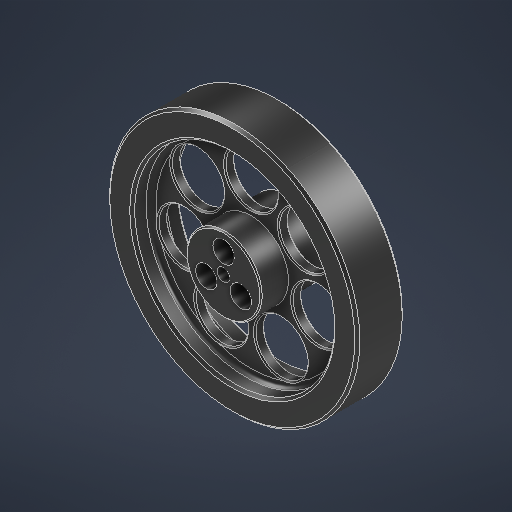
# Autodesk Inventor part: Flywheel with Cylinder
Saved by Autodesk Inventor 2026.3 (Build 303398000, 398)
## iProperties
Created: 2026-11-01
Part Number: Flywheel with Cylinder
Material: Steel
Document SubType Name: Modeling
Designer: ADMIN
Density: 7.85 g/cm^3
Appearance: Glossy - Black
Author: ADMIN
Autodesk Inventor part; units mm, degrees
ref_plane "YZ Plane" through (0, 0, 0) normal (1, 0, 0) x (0, 1, 0)
ref_plane "XZ Plane" through (0, 0, 0) normal (0, 1, 0) x (-1, 0, 0)
ref_plane "XY Plane" through (0, 0, 0) normal (0, 0, 1) x (1, 0, 0)
sketch "Sketch1" plane through (0, 0, 0) normal (0, 0, 1) x (1, 0, 0)
  circle A0 centre (0, 0) radius 50
  dimension "d0" = 100
  constraints: 1 centre point, 1 coincident
  measures "d0" diameter of A0
extrude "Extrusion1" add sketch "Sketch1" along normal mid plane 26
sketch "Sketch2" plane through (0, 0, 13) normal (0, 0, 1) x (1, 0, 0)
  circle A0 centre (0, 0) radius 15
  circle A1 centre (0, 0) radius 50 projected
  dimension "d3" = 30
  constraints: 1 centre point, 1 coincident
  measures "d3" diameter of A0
extrude "Extrusion2" cut sketch "Sketch2" against normal blind 3.5
mirror "Mirror1" about plane through (0, 0, 0) normal (0, 0, 1) of "Extrusion2"
sketch "Sketch3" plane through (0, 0, 9.5) normal (0, 0, 1) x (1, 0, 0)
  circle A0 centre (0, 0) radius 40
  circle A1 centre (0, 0) radius 50 projected
  circle A2 centre (0, 0) radius 15 projected
  dimension "d6" = 80
  constraints: 1 centre point, 1 coincident
  measures "d6" diameter of A0
extrude "Extrusion3" cut sketch "Sketch3" against normal blind 7.5 contours A0
mirror "Mirror2" about plane through (0, 0, 0) normal (0, 0, 1) of "Extrusion3"
sketch "Sketch4" plane through (0, 0, 2) normal (0, 0, 1) x (1, 0, 0)
  circle A0 centre (0, 27.5) radius 10.5
  circle A1 centre (-21.5004, 17.146) radius 10.5
  circle A2 centre (-26.8105, -6.1193) radius 10.5
  circle A3 centre (-11.9318, -24.7766) radius 10.5
  circle A4 centre (11.9318, -24.7766) radius 10.5
  circle A5 centre (26.8105, -6.1193) radius 10.5
  circle A6 centre (21.5004, 17.146) radius 10.5
  point P0 (0, 0)
  dimension "d9" = 27.5
  dimension "d10" = 21
  dimension "d13" = 360
  constraints: 7 centre point, 1 vertical alignment, 15 other
  measures "d9" distance of point (0, 0) A0.centre
  measures "d10" diameter of A0
extrude "Extrusion4" cut sketch "Sketch4" against normal through all
sketch "Sketch5" plane through (0, 0, 13) normal (0, 0, 1) x (1, 0, 0)
  point P0 (0, 0)
  point P1 (0, 8)
  point P2 (-6.9282, -4)
  point P3 (6.9282, -4)
  dimension "d17" = 8
  dimension "d20" = 360
  constraints: 1 vertical alignment, 4 other
  measures "d17" distance of point (0, 0) point (0, 8)
hole "Hole1" at (0, 8, 13) at (-6.9282, -4, 13) at (6.9282, -4, 13) direction (0, 0, -1) diameter 8.5 end through all
sketch "Sketch6" plane through (0, 0, 13) normal (0, 0, 1) x (1, 0, 0)
  point P0 (0, 0)
  point P1 (0, 0)
  constraints: 1 coincident
hole "Hole2" at (0, 0, 13) direction (0, 0, -1) diameter 5 end through all
chamfer "Chamfer1" distance 1 angle 45 4 edges at (-50, 0, 9.5) (-50, 0, -9.5) (-40, 0, 9.5) (-40, 0, -9.5)
chamfer "Chamfer2" distance 0.5 angle 45 16 edges at (-32.0004, 17.146, 2) (-32.0004, 17.146, -2) (-10.5, 27.5, 2) (-10.5, 27.5, -2) (11.0004, 17.146, 2) (11.0004, 17.146, -2) (16.3105, -6.1193, 2) (16.3105, -6.1193, -2) (-37.3105, -6.1193, 2) (-37.3105, -6.1193, -2) (1.4318, -24.7766, -2) (1.4318, -24.7766, 2) (-22.4318, -24.7766, 2) (-22.4318, -24.7766, -2) (-15, 0, 13) (-15, 0, -13)
fillet "Fillet2" radius 2 2 edges at (-40, 0, 2) (-40, 0, -2)
body "Solid1"
